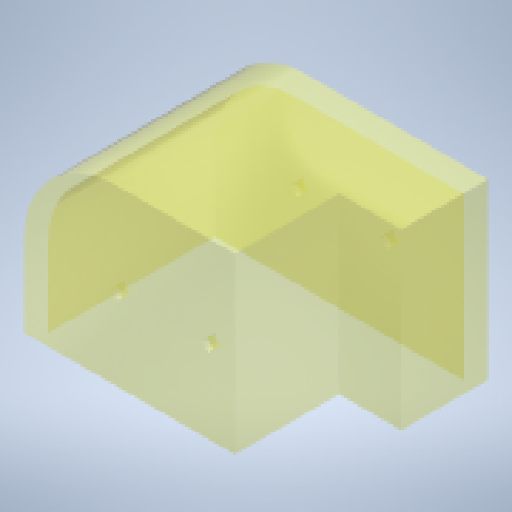
# Autodesk Inventor part: DIFF CASE
Saved by Autodesk Inventor 2026.3 (Build 303398000, 398)
## iProperties
Created: 2026-10-21
Part Number: DIFF CASE
Material: Generic
Document SubType Name: Modeling
Designer: Salim
Density: 1 g/cm^3
Appearance: Smooth - Yellow
Author: Salim
Autodesk Inventor part; units mm, degrees
ref_plane "YZ Plane" through (0, 0, 0) normal (1, 0, 0) x (0, 1, 0)
ref_plane "XZ Plane" through (0, 0, 0) normal (0, 1, 0) x (-1, 0, 0)
ref_plane "XY Plane" through (0, 0, 0) normal (0, 0, 1) x (1, 0, 0)
sketch "Sketch1" plane through (0, 0, 0) normal (0, 1, 0) x (-1, 0, 0)
  line L0 (-37.5, -25) -> (37.5, -25)
  line L1 (37.5, -25) -> (37.5, 25)
  line L2 (37.5, 25) -> (-37.5, 25)
  line L3 (-37.5, 25) -> (-37.5, -25)
  line L4 (-37.5, -25) -> (37.5, 25) construction
  line L5 (37.5, -25) -> (-37.5, 25) construction
  line L6 (37.5, -25) -> (32.5, -25)
  line L7 (32.5, -25) -> (32.5, -17)
  line L8 (32.5, -17) -> (37.5, -17)
  line L9 (37.5, -17) -> (37.5, -25)
  line L10 (32.5, -17) -> (-67.5, -17)
  line L11 (-67.5, -17) -> (-67.5, -42)
  line L12 (-67.5, -42) -> (32.5, -42)
  line L13 (32.5, -42) -> (32.5, -17)
  line L14 (32.5, -17) -> (-42.5, -17)
  line L15 (-42.5, -17) -> (-42.5, 25)
  line L16 (-42.5, 25) -> (32.5, 25)
  line L17 (32.5, 25) -> (32.5, -17)
  point P0 (0, 0)
  point P1 (-37.5, -17)
  dimension "d0" = 75
  dimension "d1" = 50
  dimension "d2" = 5
  dimension "d3" = 8
  dimension "d4" = 100
  dimension "d5" = 25
  dimension "d9" = 75
  constraints: 36 end point, 8 parallel, 4 horizontal, 4 perpendicular, 2 midpoint, 1 point on line
  measures "d0" distance of L2.end L1.end
  measures "d1" distance of L1.end L0.end
  measures "d2" distance of L7.end L8.end
  measures "d3" distance of L6.end L7.end
  measures "d4" distance of L12.end L11.end
  measures "d5" distance of L11.end L10.end
  measures "d9" distance of L15.end L16.end
extrude "Extrusion1" add sketch "Sketch1" along normal mid plane 65 contours L3 L10 L7 L0 | L0 L13 L12 L11 L10 L3 | L10 L15 L16 L3 | L3 L2 L17 L10
sketch "Sketch2" plane through (-37.5, 32.5, 25) normal (0, 0, 1) x (1, 0, 0)
  line L0 (5, -65) -> (5, 0) projected
  line L1 (5, -65) -> (205, -65)
  line L2 (205, -65) -> (205, 0)
  line L3 (205, 0) -> (5, 0)
  line L4 (5, 0) -> (5, -65)
  line L5 (75, -65) -> (75, 0) projected
  line L6 (5, 0) -> (75, 0) projected
  line L7 (5, 0) -> (5, -65) projected
  line L8 (75, -65) -> (5, -65) projected
  circle A0 centre (37.5, -32.5) radius 2 projected
  circle A1 centre (37.5, -32.5) radius 32.5
  point P0 (37.5, 0)
  point P1 (5, -32.5)
  dimension "d14" = 200
  dimension "d15" = 65
  dimension "d16" = 65
  constraints: 8 end point, 2 parallel, 1 centre point, 1 coincident, 1 horizontal, 1 perpendicular
  measures "d14" distance of L3.end L2.end
  measures "d15" distance of L2.end L1.end
  measures "d16" diameter of A1
extrude "Extrusion2" cut sketch "Sketch2" against normal blind 100 contours L0 A1 L1 | A1 | A1 L3 L5 L1 | L5 L3 L2 L1 keep common part
shell "Shell2" thickness 5 outward yes removed faces 1 at (-7.5, -32.5, -11.3333)
sketch "Sketch3" plane through (72.5, -32.5, -47) normal (0, 0, -1) x (-1, 0, 0)
  circle A0 centre (72.5, 32.5) radius 2
  circle A1 centre (72.5, 32.5) radius 2
  circle A2 centre (36.1, 32.5) radius 2 projected
  circle A3 centre (36.1, 32.5) radius 2
  point P0 (72.5, 32.5)
  dimension "d18" = 4
  dimension "d21" = 4
  constraints: 3 centre point, 2 coincident
  measures "d18" diameter of A1
  measures "d21" diameter of A3
extrude "Extrusion3" cut sketch "Sketch3" against normal through all
body "Solid1"
